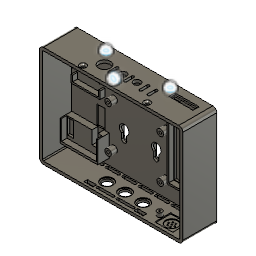
shell (Autodesk Fusion 360 design; units mm, degrees)
part number: 2026-11-14-09-25-26-611
part number: 2026-11-14-09-25-26-750
Autodesk Fusion 360 part; units mm, degrees
sketch "Sketch1" plane through (0, 0, 0) normal (0, 0, 1) x (1, 0, 0) in component "tray"
  arc A0 (67.5, 0) -> (71.5, 4) centre (67.5, 4) ccw
  line L0 (71.5, 4) -> (71.5, 97.3)
  arc A1 (71.5, 97.3) -> (67.5, 101.3) centre (67.5, 97.3) ccw
  line L1 (67.5, 101.3) -> (-67.5, 101.3)
  arc A2 (-67.5, 101.3) -> (-71.5, 97.3) centre (-67.5, 97.3) ccw
  line L2 (-71.5, 97.3) -> (-71.5, 4)
  arc A3 (-71.5, 4) -> (-67.5, 0) centre (-67.5, 4) ccw
  line L3 (-67.5, 0) -> (67.5, 0)
extrude "Extrude1" add sketch "Sketch1" along normal blind 34 from surface at 3 makes body 1 in component "tray"
sketch "Sketch3" plane through (0, 0, 0) normal (0, 0, 1) x (1, 0, 0) in component "tray"
  arc A0 (67.5, 3) -> (68.5, 4) centre (67.5, 4) ccw
  line L0 (68.5, 4) -> (68.5, 97.3)
  arc A1 (68.5, 97.3) -> (67.5, 98.3) centre (67.5, 97.3) ccw
  line L1 (67.5, 98.3) -> (-67.5, 98.3)
  arc A2 (-67.5, 98.3) -> (-68.5, 97.3) centre (-67.5, 97.3) ccw
  line L2 (-68.5, 97.3) -> (-68.5, 4)
  arc A3 (-68.5, 4) -> (-67.5, 3) centre (-67.5, 4) ccw
  line L3 (-67.5, 3) -> (67.5, 3)
extrude "Extrude2" add sketch "Sketch3" along normal blind 29.1 from surface at 2.9 separate body makes body 2 in component "tray"
combine "Combine1" operation cut target body 1 tool bodies 2 in component "tray"
sketch "Sketch4" plane through (0, 0, 0) normal (0, 0, 1) x (1, 0, 0) in component "tray"
  circle A0 centre (26, 38.5) radius 3.25
extrude "Extrude3" add sketch "Sketch4" along normal blind 6.01 from surface at 26 separate body makes body 3 in component "tray"
sketch "Sketch5" plane through (0, 0, 0) normal (0, 0, 1) x (1, 0, 0) in component "tray"
  circle A0 centre (26, 38.5) radius 1.3
extrude "Extrude4" add sketch "Sketch5" along normal blind 8.1 from surface at 25.9 separate body makes body 4 in component "tray"
sketch "Sketch6" plane through (0, 0, 0) normal (0, 0, 1) x (1, 0, 0) in component "tray"
  circle A0 centre (-26, 38.5) radius 3.25
extrude "Extrude5" add sketch "Sketch6" along normal blind 6.01 from surface at 26 separate body makes body 5 in component "tray"
sketch "Sketch7" plane through (0, 0, 0) normal (0, 0, 1) x (1, 0, 0) in component "tray"
  circle A0 centre (-26, 38.5) radius 1.3
extrude "Extrude6" add sketch "Sketch7" along normal blind 8.1 from surface at 25.9 separate body makes body 6 in component "tray"
sketch "Sketch8" plane through (0, 0, 0) normal (0, 0, 1) x (1, 0, 0) in component "tray"
  circle A0 centre (26, 81.5) radius 3.25
extrude "Extrude7" add sketch "Sketch8" along normal blind 6.01 from surface at 26 separate body makes body 7 in component "tray"
sketch "Sketch9" plane through (0, 0, 0) normal (0, 0, 1) x (1, 0, 0) in component "tray"
  circle A0 centre (26, 81.5) radius 1.3
extrude "Extrude8" add sketch "Sketch9" along normal blind 8.1 from surface at 25.9 separate body makes body 8 in component "tray"
sketch "Sketch10" plane through (0, 0, 0) normal (0, 0, 1) x (1, 0, 0) in component "tray"
  circle A0 centre (-26, 81.5) radius 3.25
extrude "Extrude9" add sketch "Sketch10" along normal blind 6.01 from surface at 26 separate body makes body 9 in component "tray"
sketch "Sketch11" plane through (0, 0, 0) normal (0, 0, 1) x (1, 0, 0) in component "tray"
  circle A0 centre (-26, 81.5) radius 1.3
extrude "Extrude10" add sketch "Sketch11" along normal blind 8.1 from surface at 25.9 separate body makes body 10 in component "tray"
sketch "Sketch12" plane through (0, 0, 0) normal (0, 0, 1) x (1, 0, 0) in component "tray"
  line L0 (37.1, -0.01) -> (37.1, 7.6)
  line L1 (37.1, 7.6) -> (-37.1, 7.6)
  line L2 (-37.1, 7.6) -> (-37.1, -0.01)
  line L3 (-37.1, -0.01) -> (37.1, -0.01)
extrude "Extrude11" add sketch "Sketch12" along normal blind 30.2 from surface at -15.1 separate body makes body 11 in component "tray"
sketch "Sketch13" plane through (0, 0, 0) normal (0, 0, 1) x (1, 0, 0) in component "tray"
  line L0 (35.5, 2.5) -> (35.5, 8.6)
  line L1 (35.5, 8.6) -> (-35.5, 8.6)
  line L2 (-35.5, 8.6) -> (-35.5, 2.5)
  line L3 (-35.5, 2.5) -> (35.5, 2.5)
extrude "Extrude12" add sketch "Sketch13" along normal blind 27 from surface at -13.5 separate body makes body 12 in component "tray"
sketch "Sketch14" plane through (0, 0, 0) normal (0, 0, 1) x (1, 0, 0) in component "tray"
  line L0 (35, 0.5) -> (35, 2.6)
  line L1 (35, 2.6) -> (-35, 2.6)
  line L2 (-35, 2.6) -> (-35, 0.5)
  line L3 (-35, 0.5) -> (35, 0.5)
extrude "Extrude13" add sketch "Sketch14" along normal blind 6 from surface at -13 separate body makes body 13 in component "tray"
sketch "Sketch15" plane through (0, 0, 0) normal (0, 0, 1) x (1, 0, 0) in component "tray"
  line L0 (35, 0.5) -> (35, 2.6)
  line L1 (35, 2.6) -> (-35, 2.6)
  line L2 (-35, 2.6) -> (-35, 0.5)
  line L3 (-35, 0.5) -> (35, 0.5)
extrude "Extrude14" add sketch "Sketch15" along normal blind 6 from surface at 7 separate body makes body 14 in component "tray"
sketch "Sketch16" plane through (0, 0, 0) normal (0, 0, 1) x (1, 0, 0) in component "tray"
  line L0 (-35.49, 2.5) -> (-35.49, 8.6)
  line L1 (-35.49, 8.6) -> (-37.2, 8.6)
  line L2 (-37.2, 8.6) -> (-37.2, 2.5)
  line L3 (-37.2, 2.5) -> (-35.49, 2.5)
extrude "Extrude15" add sketch "Sketch16" along normal blind 24.8 from surface at -12.4 separate body makes body 15 in component "tray"
combine "Combine2" operation cut target body 11 tool bodies 12 13 14 15 in component "tray"
move_body "Move1" bodies 11 to x (0, 1, 0) y (0, 0, -1) z (-1, 0, 0) at (49.5, 40.6, 32) in component "tray"
sketch "Sketch17" plane through (0, 0, 0) normal (0, 0, 1) x (1, 0, 0) in component "tray"
  line L0 (18.7, -0.01) -> (18.7, 11.6)
  line L1 (18.7, 11.6) -> (-18.7, 11.6)
  line L2 (-18.7, 11.6) -> (-18.7, -0.01)
  line L3 (-18.7, -0.01) -> (18.7, -0.01)
extrude "Extrude16" add sketch "Sketch17" along normal blind 21.8 from surface at -12.2 separate body makes body 16 in component "tray"
sketch "Sketch18" plane through (0, 0, 0) normal (0, 0, 1) x (1, 0, 0) in component "tray"
  line L0 (17.5, 6) -> (17.5, 11.7)
  line L1 (17.5, 11.7) -> (-17.5, 11.7)
  line L2 (-17.5, 11.7) -> (-17.5, 6)
  line L3 (-17.5, 6) -> (17.5, 6)
extrude "Extrude17" add sketch "Sketch18" along normal blind 20.6 from surface at -10 separate body makes body 17 in component "tray"
sketch "Sketch19" plane through (0, 0, 0) normal (0, 0, 1) x (1, 0, 0) in component "tray"
  line L0 (-7.5, -0.9) -> (-7.5, 6.01)
  line L1 (-7.5, 6.01) -> (-13.5, 6.01)
  line L2 (-13.5, 6.01) -> (-13.5, -0.9)
  line L3 (-13.5, -0.9) -> (-7.5, -0.9)
extrude "Extrude18" add sketch "Sketch19" along normal blind 14 from surface at -3.4 separate body makes body 18 in component "tray"
sketch "Sketch20" plane through (0, 0, 0) normal (0, 0, 1) x (1, 0, 0) in component "tray"
  line L0 (17, 3.6) -> (17, 6.01)
  line L1 (17, 6.01) -> (11, 6.01)
  line L2 (11, 6.01) -> (11, 3.6)
  line L3 (11, 3.6) -> (17, 3.6)
extrude "Extrude19" add sketch "Sketch20" along normal blind 15.2 from surface at -7 separate body makes body 19 in component "tray"
combine "Combine3" operation cut target body 16 tool bodies 17 18 19 in component "tray"
move_body "Move2" bodies 16 to x (-1, 0, 0) y (0, 0, -1) z (0, -1, 0) at (-49.5, 79.7, 32) in component "tray"
sketch "Sketch21" plane through (0, 0, 0) normal (0, 0, 1) x (1, 0, 0) in component "tray"
  line L0 (-6.5, -1.2) -> (-6.5, 0.01)
  line L1 (-6.5, 0.01) -> (-14.5, 0.01)
  line L2 (-14.5, 0.01) -> (-14.5, -1.2)
  line L3 (-14.5, -1.2) -> (-6.5, -1.2)
extrude "Extrude20" add sketch "Sketch21" along normal blind 18.5 from surface at 10 separate body makes body 20 in component "tray"
move_body "Move3" bodies 20 to x (-1, 0, 0) y (0, 0, -1) z (0, -1, 0) at (-49.5, 79.7, 32) in component "tray"
sketch "Sketch22" plane through (0, 0, 0) normal (0, 0, 1) x (1, 0, 0) in component "tray"
  line L0 (14.5, -0.01) -> (14.5, 5)
  line L1 (14.5, 5) -> (-14.5, 5)
  line L2 (-14.5, 5) -> (-14.5, -0.01)
  line L3 (-14.5, -0.01) -> (14.5, -0.01)
extrude "Extrude21" add sketch "Sketch22" along normal blind 21 from surface at -10.5 separate body makes body 21 in component "tray"
sketch "Sketch23" plane through (0, 0, 0) normal (0, 0, 1) x (1, 0, 0) in component "tray"
  line L0 (12.9, 0) -> (12.9, 5.1)
  line L1 (12.9, 5.1) -> (-12.9, 5.1)
  line L2 (-12.9, 5.1) -> (-12.9, 0)
  line L3 (-12.9, 0) -> (12.9, 0)
extrude "Extrude22" add sketch "Sketch23" along normal blind 17.8 from surface at -8.9 separate body makes body 22 in component "tray"
sketch "Sketch24" plane through (0, 0, 0) normal (0, 0, 1) x (1, 0, 0) in component "tray"
  line L0 (14.6, 0) -> (14.6, 5.1)
  line L1 (14.6, 5.1) -> (-14.6, 5.1)
  line L2 (-14.6, 5.1) -> (-14.6, 0)
  line L3 (-14.6, 0) -> (14.6, 0)
extrude "Extrude23" add sketch "Sketch24" along normal blind 6 from surface at -3 separate body makes body 23 in component "tray"
move_body "Move4" bodies 21 22 23 to x (1, 0, 0) y (0, 0, -1) z (0, 1, 0) at (-49.5, 30.5, 32) in component "tray"
sketch "Sketch25" plane through (0, 0, 0) normal (0, 1, 0) x (1, 0, 0) in component "tray"
  circle A0 centre (37.5, -14) radius 2.5
extrude "Extrude24" add sketch "Sketch25" along normal blind 4.01 from surface at 94.3 separate body makes body 24 in component "tray"
sketch "Sketch27" plane through (0, 0, 0) normal (0, 1, 0) x (1, 0, 0) in component "tray"
  circle A0 centre (37.5, -14) radius 0.8
extrude "Extrude25" add sketch "Sketch27" along normal blind 4.1 from surface at 94.2 separate body makes body 25 in component "tray"
sketch "Sketch28" plane through (0, 0, 0) normal (0, 1, 0) x (1, 0, 0) in component "tray"
  circle A0 centre (61.5, -14) radius 2.5
extrude "Extrude26" add sketch "Sketch28" along normal blind 4.01 from surface at 94.3 separate body makes body 26 in component "tray"
sketch "Sketch29" plane through (0, 0, 0) normal (0, 1, 0) x (1, 0, 0) in component "tray"
  circle A0 centre (61.5, -14) radius 0.8
extrude "Extrude27" add sketch "Sketch29" along normal blind 4.1 from surface at 94.2 separate body makes body 27 in component "tray"
combine "Combine4" operation add target body 1 tool bodies 3 5 7 9 11 16 21 24 26 in component "tray"
sketch "Sketch30" plane through (0, 0, 0) normal (0, 0, 1) x (1, 0, 0) in component "tray"
  circle A0 centre (16, 60) radius 4.75
extrude "Extrude28" add sketch "Sketch30" along normal blind 5.2 from surface at 31.9 separate body makes body 28 in component "tray"
sketch "Sketch31" plane through (0, 0, 0) normal (0, 0, 1) x (1, 0, 0) in component "tray"
  arc A0 (13.5, 60) -> (16, 57.5) centre (16, 60) ccw
  arc A1 (16, 57.5) -> (18.5, 60) centre (16, 60) ccw
  line L0 (18.5, 60) -> (18.5, 69)
  arc A2 (18.5, 69) -> (16, 71.5) centre (16, 69) ccw
  arc A3 (16, 71.5) -> (13.5, 69) centre (16, 69) ccw
  line L1 (13.5, 69) -> (13.5, 60)
extrude "Extrude29" add sketch "Sketch31" along normal blind 5.2 from surface at 31.9 separate body makes body 29 in component "tray"
sketch "Sketch32" plane through (0, 0, 0) normal (0, 0, 1) x (1, 0, 0) in component "tray"
  arc A0 (11.25, 60) -> (16, 55.25) centre (16, 60) ccw
  arc A1 (16, 55.25) -> (20.75, 60) centre (16, 60) ccw
  line L0 (20.75, 60) -> (20.75, 69)
  arc A2 (20.75, 69) -> (16, 73.75) centre (16, 69) ccw
  arc A3 (16, 73.75) -> (11.25, 69) centre (16, 69) ccw
  line L1 (11.25, 69) -> (11.25, 60)
extrude "Extrude30" add sketch "Sketch32" along normal blind 3.1 from surface at 34 separate body makes body 30 in component "tray"
sketch "Sketch33" plane through (0, 0, 0) normal (0, 0, 1) x (1, 0, 0) in component "tray"
  circle A0 centre (-16, 60) radius 4.75
extrude "Extrude31" add sketch "Sketch33" along normal blind 5.2 from surface at 31.9 separate body makes body 31 in component "tray"
sketch "Sketch34" plane through (0, 0, 0) normal (0, 0, 1) x (1, 0, 0) in component "tray"
  arc A0 (-18.5, 60) -> (-16, 57.5) centre (-16, 60) ccw
  arc A1 (-16, 57.5) -> (-13.5, 60) centre (-16, 60) ccw
  line L0 (-13.5, 60) -> (-13.5, 69)
  arc A2 (-13.5, 69) -> (-16, 71.5) centre (-16, 69) ccw
  arc A3 (-16, 71.5) -> (-18.5, 69) centre (-16, 69) ccw
  line L1 (-18.5, 69) -> (-18.5, 60)
extrude "Extrude32" add sketch "Sketch34" along normal blind 5.2 from surface at 31.9 separate body makes body 32 in component "tray"
sketch "Sketch35" plane through (0, 0, 0) normal (0, 0, 1) x (1, 0, 0) in component "tray"
  arc A0 (-20.75, 60) -> (-16, 55.25) centre (-16, 60) ccw
  arc A1 (-16, 55.25) -> (-11.25, 60) centre (-16, 60) ccw
  line L0 (-11.25, 60) -> (-11.25, 69)
  arc A2 (-11.25, 69) -> (-16, 73.75) centre (-16, 69) ccw
  arc A3 (-16, 73.75) -> (-20.75, 69) centre (-16, 69) ccw
  line L1 (-20.75, 69) -> (-20.75, 60)
extrude "Extrude33" add sketch "Sketch35" along normal blind 3.1 from surface at 34 separate body makes body 33 in component "tray"
sketch "Sketch36" plane through (0, 0, 0) normal (0, 0, 1) x (1, 0, 0) in component "tray"
  circle A0 centre (2.5, 8) radius 2.25
extrude "Extrude34" add sketch "Sketch36" along normal blind 5.2 from surface at 31.9 separate body makes body 34 in component "tray"
ref_plane "WorkPlane1" through (0, 0, 31.99) normal (0, 0, 1) x (1, 0, 0) in component "tray"
sketch "Sketch37" plane through (0, 0, 31.99) normal (0, 0, 1) x (1, 0, 0) in component "tray"
  circle A0 centre (2.5, 8) radius 4.51
ref_plane "WorkPlane2" through (0, 0, 34.25) normal (0, 0, 1) x (1, 0, 0) in component "tray"
sketch "Sketch38" plane through (0, 0, 34.25) normal (0, 0, 1) x (1, 0, 0) in component "tray"
  circle A0 centre (2.5, 8) radius 2.25
loft "Loft1" add profiles "Sketch37", "Sketch38" section 1 section 2 separate body makes body 35 in component "tray"
sketch "Sketch39" plane through (0, 0, 0) normal (0, 0, 1) x (1, 0, 0) in component "tray"
  circle A0 centre (-14, 12.5) radius 6
extrude "Extrude35" add sketch "Sketch39" along normal blind 4.5 from surface at 31.9 separate body makes body 36 in component "tray"
sketch "Sketch40" plane through (0, 0, 0) normal (0, 0, 1) x (1, 0, 0) in component "tray"
  circle A0 centre (14, 12.5) radius 6
extrude "Extrude36" add sketch "Sketch40" along normal blind 4.5 from surface at 31.9 separate body makes body 37 in component "tray"
sketch "Sketch41" plane through (0, 0, 0) normal (0, 1, 0) x (1, 0, 0) in component "tray"
  circle A0 centre (18, -17) radius 4.5
extrude "Extrude37" add sketch "Sketch41" along normal blind 3.2 from surface at 98.2 separate body makes body 38 in component "tray"
sketch "Sketch42" plane through (0, 0, 0) normal (0, 1, 0) x (1, 0, 0) in component "tray"
  circle A0 centre (0, -17) radius 4.5
extrude "Extrude38" add sketch "Sketch42" along normal blind 3.2 from surface at 98.2 separate body makes body 39 in component "tray"
sketch "Sketch43" plane through (0, 0, 0) normal (0, 1, 0) x (1, 0, 0) in component "tray"
  circle A0 centre (-18, -17) radius 4.5
extrude "Extrude39" add sketch "Sketch43" along normal blind 3.2 from surface at 98.2 separate body makes body 40 in component "tray"
sketch "Sketch44" plane through (0, 0, 0) normal (0, 1, 0) x (1, 0, 0) in component "tray"
  circle A0 centre (18, -17) radius 6
extrude "Extrude40" add sketch "Sketch44" along normal blind 0.9 from surface at 98.2 separate body makes body 41 in component "tray"
sketch "Sketch45" plane through (0, 0, 0) normal (0, 1, 0) x (1, 0, 0) in component "tray"
  circle A0 centre (0, -17) radius 6
extrude "Extrude41" add sketch "Sketch45" along normal blind 0.9 from surface at 98.2 separate body makes body 42 in component "tray"
sketch "Sketch46" plane through (0, 0, 0) normal (0, 1, 0) x (1, 0, 0) in component "tray"
  circle A0 centre (-18, -17) radius 6
extrude "Extrude42" add sketch "Sketch46" along normal blind 0.9 from surface at 98.2 separate body makes body 43 in component "tray"
sketch "Sketch47" plane through (0, 0, 0) normal (0, 1, 0) x (1, 0, 0) in component "tray"
  arc A0 (-1, -7.5) -> (-2.25, -6.25) centre (-2.25, -7.5) ccw
  arc A1 (-2.25, -8.75) -> (-1, -7.5) centre (-2.25, -7.5) ccw
  line L0 (-2.25, -8.75) -> (-17.75, -8.75)
  arc A2 (-19, -7.5) -> (-17.75, -8.75) centre (-17.75, -7.5) ccw
  arc A3 (-17.75, -6.25) -> (-19, -7.5) centre (-17.75, -7.5) ccw
  line L1 (-17.75, -6.25) -> (-2.25, -6.25)
extrude "Extrude43" add sketch "Sketch47" along normal blind 3.2 from surface at 98.2 separate body makes body 44 in component "tray"
sketch "Sketch48" plane through (0, 0, 0) normal (0, 1, 0) x (1, 0, 0) in component "tray"
  arc A0 (19, -7.5) -> (17.75, -6.25) centre (17.75, -7.5) ccw
  arc A1 (17.75, -8.75) -> (19, -7.5) centre (17.75, -7.5) ccw
  line L0 (17.75, -8.75) -> (2.25, -8.75)
  arc A2 (1, -7.5) -> (2.25, -8.75) centre (2.25, -7.5) ccw
  arc A3 (2.25, -6.25) -> (1, -7.5) centre (2.25, -7.5) ccw
  line L1 (2.25, -6.25) -> (17.75, -6.25)
extrude "Extrude44" add sketch "Sketch48" along normal blind 3.2 from surface at 98.2 separate body makes body 45 in component "tray"
sketch "Sketch49" plane through (0, 0, 0) normal (0, 1, 0) x (1, 0, 0) in component "tray"
  arc A0 (-50.125, -29.5) -> (-51.375, -28.25) centre (-51.375, -29.5) ccw
  arc A1 (-51.375, -30.75) -> (-50.125, -29.5) centre (-51.375, -29.5) ccw
  line L0 (-51.375, -30.75) -> (-63.25, -30.75)
  arc A2 (-64.5, -29.5) -> (-63.25, -30.75) centre (-63.25, -29.5) ccw
  arc A3 (-63.25, -28.25) -> (-64.5, -29.5) centre (-63.25, -29.5) ccw
  line L1 (-63.25, -28.25) -> (-51.375, -28.25)
extrude "Extrude45" add sketch "Sketch49" along normal blind 3.2 from surface at 98.2 separate body makes body 46 in component "tray"
sketch "Sketch50" plane through (0, 0, 0) normal (0, 1, 0) x (1, 0, 0) in component "tray"
  arc A0 (-33.75, -29.5) -> (-35, -28.25) centre (-35, -29.5) ccw
  arc A1 (-35, -30.75) -> (-33.75, -29.5) centre (-35, -29.5) ccw
  line L0 (-35, -30.75) -> (-46.875, -30.75)
  arc A2 (-48.125, -29.5) -> (-46.875, -30.75) centre (-46.875, -29.5) ccw
  arc A3 (-46.875, -28.25) -> (-48.125, -29.5) centre (-46.875, -29.5) ccw
  line L1 (-46.875, -28.25) -> (-35, -28.25)
extrude "Extrude46" add sketch "Sketch50" along normal blind 3.2 from surface at 98.2 separate body makes body 47 in component "tray"
sketch "Sketch51" plane through (0, 0, 0) normal (0, 1, 0) x (1, 0, 0) in component "tray"
  arc A0 (-17.375, -29.5) -> (-18.625, -28.25) centre (-18.625, -29.5) ccw
  arc A1 (-18.625, -30.75) -> (-17.375, -29.5) centre (-18.625, -29.5) ccw
  line L0 (-18.625, -30.75) -> (-30.5, -30.75)
  arc A2 (-31.75, -29.5) -> (-30.5, -30.75) centre (-30.5, -29.5) ccw
  arc A3 (-30.5, -28.25) -> (-31.75, -29.5) centre (-30.5, -29.5) ccw
  line L1 (-30.5, -28.25) -> (-18.625, -28.25)
extrude "Extrude47" add sketch "Sketch51" along normal blind 3.2 from surface at 98.2 separate body makes body 48 in component "tray"
sketch "Sketch52" plane through (0, 0, 0) normal (0, 1, 0) x (1, 0, 0) in component "tray"
  arc A0 (-1, -29.5) -> (-2.25, -28.25) centre (-2.25, -29.5) ccw
  arc A1 (-2.25, -30.75) -> (-1, -29.5) centre (-2.25, -29.5) ccw
  line L0 (-2.25, -30.75) -> (-14.125, -30.75)
  arc A2 (-15.375, -29.5) -> (-14.125, -30.75) centre (-14.125, -29.5) ccw
  arc A3 (-14.125, -28.25) -> (-15.375, -29.5) centre (-14.125, -29.5) ccw
  line L1 (-14.125, -28.25) -> (-2.25, -28.25)
extrude "Extrude48" add sketch "Sketch52" along normal blind 3.2 from surface at 98.2 separate body makes body 49 in component "tray"
sketch "Sketch53" plane through (0, 0, 0) normal (0, 1, 0) x (1, 0, 0) in component "tray"
  arc A0 (15.375, -29.5) -> (14.125, -28.25) centre (14.125, -29.5) ccw
  arc A1 (14.125, -30.75) -> (15.375, -29.5) centre (14.125, -29.5) ccw
  line L0 (14.125, -30.75) -> (2.25, -30.75)
  arc A2 (1, -29.5) -> (2.25, -30.75) centre (2.25, -29.5) ccw
  arc A3 (2.25, -28.25) -> (1, -29.5) centre (2.25, -29.5) ccw
  line L1 (2.25, -28.25) -> (14.125, -28.25)
extrude "Extrude49" add sketch "Sketch53" along normal blind 3.2 from surface at 98.2 separate body makes body 50 in component "tray"
sketch "Sketch54" plane through (0, 0, 0) normal (0, 1, 0) x (1, 0, 0) in component "tray"
  arc A0 (31.75, -29.5) -> (30.5, -28.25) centre (30.5, -29.5) ccw
  arc A1 (30.5, -30.75) -> (31.75, -29.5) centre (30.5, -29.5) ccw
  line L0 (30.5, -30.75) -> (18.625, -30.75)
  arc A2 (17.375, -29.5) -> (18.625, -30.75) centre (18.625, -29.5) ccw
  arc A3 (18.625, -28.25) -> (17.375, -29.5) centre (18.625, -29.5) ccw
  line L1 (18.625, -28.25) -> (30.5, -28.25)
extrude "Extrude50" add sketch "Sketch54" along normal blind 3.2 from surface at 98.2 separate body makes body 51 in component "tray"
sketch "Sketch55" plane through (0, 0, 0) normal (0, 1, 0) x (1, 0, 0) in component "tray"
  arc A0 (48.125, -29.5) -> (46.875, -28.25) centre (46.875, -29.5) ccw
  arc A1 (46.875, -30.75) -> (48.125, -29.5) centre (46.875, -29.5) ccw
  line L0 (46.875, -30.75) -> (35, -30.75)
  arc A2 (33.75, -29.5) -> (35, -30.75) centre (35, -29.5) ccw
  arc A3 (35, -28.25) -> (33.75, -29.5) centre (35, -29.5) ccw
  line L1 (35, -28.25) -> (46.875, -28.25)
extrude "Extrude51" add sketch "Sketch55" along normal blind 3.2 from surface at 98.2 separate body makes body 52 in component "tray"
sketch "Sketch56" plane through (0, 0, 0) normal (0, 1, 0) x (1, 0, 0) in component "tray"
  arc A0 (64.5, -29.5) -> (63.25, -28.25) centre (63.25, -29.5) ccw
  arc A1 (63.25, -30.75) -> (64.5, -29.5) centre (63.25, -29.5) ccw
  line L0 (63.25, -30.75) -> (51.375, -30.75)
  arc A2 (50.125, -29.5) -> (51.375, -30.75) centre (51.375, -29.5) ccw
  arc A3 (51.375, -28.25) -> (50.125, -29.5) centre (51.375, -29.5) ccw
  line L1 (51.375, -28.25) -> (63.25, -28.25)
extrude "Extrude52" add sketch "Sketch56" along normal blind 3.2 from surface at 98.2 separate body makes body 53 in component "tray"
sketch "Sketch57" plane through (0, 0, 0) normal (0, 0, 1) x (1, 0, 0) in component "tray"
  line L0 (-20.5, 98.2) -> (-20.5, 101.4)
  line L1 (-20.5, 101.4) -> (-29.5, 101.4)
  line L2 (-29.5, 101.4) -> (-29.5, 98.2)
  line L3 (-29.5, 98.2) -> (-20.5, 98.2)
extrude "Extrude53" add sketch "Sketch57" along normal blind 3.5 from surface at 5.5 separate body makes body 54 in component "tray"
sketch "Sketch58" plane through (0, 0, 0) normal (0, 0, 1) x (1, 0, 0) in component "tray"
  line L0 (29.5, 98.2) -> (29.5, 101.4)
  line L1 (29.5, 101.4) -> (20.5, 101.4)
  line L2 (20.5, 101.4) -> (20.5, 98.2)
  line L3 (20.5, 98.2) -> (29.5, 98.2)
extrude "Extrude54" add sketch "Sketch58" along normal blind 3.5 from surface at 5.5 separate body makes body 55 in component "tray"
sketch "Sketch59" plane through (0, 0, 0) normal (0, 1, 0) x (1, 0, 0) in component "tray"
  line L0 (58.4, -6.1) -> (58.4, -21.9)
  line L1 (58.4, -21.9) -> (40.6, -21.9)
  line L2 (40.6, -21.9) -> (40.6, -6.1)
  line L3 (40.6, -6.1) -> (58.4, -6.1)
extrude "Extrude55" add sketch "Sketch59" along normal blind 1.1 from surface at 98.2 separate body makes body 56 in component "tray"
sketch "Sketch60" plane through (0, 0, 0) normal (0, 1, 0) x (1, 0, 0) in component "tray"
  circle A0 centre (49.5, -14) radius 6
extrude "Extrude56" add sketch "Sketch60" along normal blind 0.81 from surface at 99.29 separate body makes body 57 in component "tray"
sketch "Sketch61" plane through (0, 0, 0) normal (0, 1, 0) x (1, 0, 0) in component "tray"
  circle A0 centre (49.5, -14) radius 0.75
extrude "Extrude57" add sketch "Sketch61" along normal blind 1.31 from surface at 100.09 separate body makes body 58 in component "tray"
sketch "Sketch62" plane through (0, 0, 0) normal (0, 1, 0) x (1, 0, 0) in component "tray"
  circle A0 centre (52.5, -14) radius 0.75
extrude "Extrude58" add sketch "Sketch62" along normal blind 1.31 from surface at 100.09 separate body makes body 59 in component "tray"
sketch "Sketch63" plane through (0, 0, 0) normal (0, 1, 0) x (1, 0, 0) in component "tray"
  circle A0 centre (51, -16.5981) radius 0.75
extrude "Extrude59" add sketch "Sketch63" along normal blind 1.31 from surface at 100.09 separate body makes body 60 in component "tray"
sketch "Sketch64" plane through (0, 0, 0) normal (0, 1, 0) x (1, 0, 0) in component "tray"
  circle A0 centre (48, -16.5981) radius 0.75
extrude "Extrude60" add sketch "Sketch64" along normal blind 1.31 from surface at 100.09 separate body makes body 61 in component "tray"
sketch "Sketch65" plane through (0, 0, 0) normal (0, 1, 0) x (1, 0, 0) in component "tray"
  circle A0 centre (46.5, -14) radius 0.75
extrude "Extrude61" add sketch "Sketch65" along normal blind 1.31 from surface at 100.09 separate body makes body 62 in component "tray"
sketch "Sketch66" plane through (0, 0, 0) normal (0, 1, 0) x (1, 0, 0) in component "tray"
  circle A0 centre (48, -11.4019) radius 0.75
extrude "Extrude62" add sketch "Sketch66" along normal blind 1.31 from surface at 100.09 separate body makes body 63 in component "tray"
sketch "Sketch67" plane through (0, 0, 0) normal (0, 1, 0) x (1, 0, 0) in component "tray"
  circle A0 centre (51, -11.4019) radius 0.75
extrude "Extrude63" add sketch "Sketch67" along normal blind 1.31 from surface at 100.09 separate body makes body 64 in component "tray"
sketch "Sketch68" plane through (0, 0, 0) normal (0, 1, 0) x (1, 0, 0) in component "tray"
  circle A0 centre (-22, -18.4) radius 6
extrude "Extrude64" add sketch "Sketch68" along normal blind 3.2 from surface at -0.1 separate body makes body 65 in component "tray"
sketch "Sketch69" plane through (0, 0, 0) normal (0, 1, 0) x (1, 0, 0) in component "tray"
  circle A0 centre (-4.5, -19.4) radius 3.5
extrude "Extrude65" add sketch "Sketch69" along normal blind 3.2 from surface at -0.1 separate body makes body 66 in component "tray"
sketch "Sketch70" plane through (0, 0, 0) normal (0, 1, 0) x (1, 0, 0) in component "tray"
  circle A0 centre (9.5, -19.4) radius 3.5
extrude "Extrude66" add sketch "Sketch70" along normal blind 3.2 from surface at -0.1 separate body makes body 67 in component "tray"
sketch "Sketch71" plane through (0, 0, 0) normal (0, 1, 0) x (1, 0, 0) in component "tray"
  arc A0 (-13, -13.4) -> (-14.25, -14.65) centre (-13, -14.65) ccw
  arc A1 (-11.75, -14.65) -> (-13, -13.4) centre (-13, -14.65) ccw
  line L0 (-11.75, -14.65) -> (-11.75, -22.15)
  arc A2 (-13, -23.4) -> (-11.75, -22.15) centre (-13, -22.15) ccw
  arc A3 (-14.25, -22.15) -> (-13, -23.4) centre (-13, -22.15) ccw
  line L1 (-14.25, -22.15) -> (-14.25, -14.65)
extrude "Extrude67" add sketch "Sketch71" along normal blind 3.2 from surface at -0.1 separate body makes body 68 in component "tray"
sketch "Sketch72" plane through (0, 0, 0) normal (0, 1, 0) x (1, 0, 0) in component "tray"
  arc A0 (2.5, -13.4) -> (1.25, -14.65) centre (2.5, -14.65) ccw
  arc A1 (3.75, -14.65) -> (2.5, -13.4) centre (2.5, -14.65) ccw
  line L0 (3.75, -14.65) -> (3.75, -22.15)
  arc A2 (2.5, -23.4) -> (3.75, -22.15) centre (2.5, -22.15) ccw
  arc A3 (1.25, -22.15) -> (2.5, -23.4) centre (2.5, -22.15) ccw
  line L1 (1.25, -22.15) -> (1.25, -14.65)
extrude "Extrude68" add sketch "Sketch72" along normal blind 3.2 from surface at -0.1 separate body makes body 69 in component "tray"
sketch "Sketch73" plane through (0, 0, 0) normal (0, 1, 0) x (1, 0, 0) in component "tray"
  arc A0 (18, -13.4) -> (16.75, -14.65) centre (18, -14.65) ccw
  arc A1 (19.25, -14.65) -> (18, -13.4) centre (18, -14.65) ccw
  line L0 (19.25, -14.65) -> (19.25, -22.15)
  arc A2 (18, -23.4) -> (19.25, -22.15) centre (18, -22.15) ccw
  arc A3 (16.75, -22.15) -> (18, -23.4) centre (18, -22.15) ccw
  line L1 (16.75, -22.15) -> (16.75, -14.65)
extrude "Extrude69" add sketch "Sketch73" along normal blind 3.2 from surface at -0.1 separate body makes body 70 in component "tray"
sketch "Sketch74" plane through (0, 0, 0) normal (0, 1, 0) x (1, 0, 0) in component "tray"
  arc A0 (26, -13.4) -> (24.75, -14.65) centre (26, -14.65) ccw
  arc A1 (27.25, -14.65) -> (26, -13.4) centre (26, -14.65) ccw
  line L0 (27.25, -14.65) -> (27.25, -22.15)
  arc A2 (26, -23.4) -> (27.25, -22.15) centre (26, -22.15) ccw
  arc A3 (24.75, -22.15) -> (26, -23.4) centre (26, -22.15) ccw
  line L1 (24.75, -22.15) -> (24.75, -14.65)
extrude "Extrude70" add sketch "Sketch74" along normal blind 3.2 from surface at -0.1 separate body makes body 71 in component "tray"
sketch "Sketch75" plane through (0, 0, 0) normal (0, 1, 0) x (1, 0, 0) in component "tray"
  circle A0 centre (-32, -7) radius 1.7
extrude "Extrude71" add sketch "Sketch75" along normal blind 3.2 from surface at -0.1 separate body makes body 72 in component "tray"
ref_plane "WorkPlane3" through (0, -0.1, 0) normal (0, 1, 0) x (0, 0, 1) in component "tray"
sketch "Sketch76" plane through (0, -0.1, 0) normal (0, 1, 0) x (1, 0, 0) in component "tray"
  circle A0 centre (-32, -7) radius 3.35
ref_plane "WorkPlane4" through (0, 1.55, 0) normal (0, 1, 0) x (0, 0, 1) in component "tray"
sketch "Sketch77" plane through (0, 1.55, 0) normal (0, 1, 0) x (1, 0, 0) in component "tray"
  circle A0 centre (-32, -7) radius 1.7
loft "Loft2" add profiles "Sketch76", "Sketch77" section 1 section 2 separate body makes body 73 in component "tray"
sketch "Sketch78" plane through (0, 0, 0) normal (0, 1, 0) x (1, 0, 0) in component "tray"
  circle A0 centre (32, -7) radius 1.7
extrude "Extrude72" add sketch "Sketch78" along normal blind 3.2 from surface at -0.1 separate body makes body 74 in component "tray"
ref_plane "WorkPlane5" through (0, -0.1, 0) normal (0, 1, 0) x (0, 0, 1) in component "tray"
sketch "Sketch79" plane through (0, -0.1, 0) normal (0, 1, 0) x (1, 0, 0) in component "tray"
  circle A0 centre (32, -7) radius 3.35
ref_plane "WorkPlane6" through (0, 1.55, 0) normal (0, 1, 0) x (0, 0, 1) in component "tray"
sketch "Sketch80" plane through (0, 1.55, 0) normal (0, 1, 0) x (1, 0, 0) in component "tray"
  circle A0 centre (32, -7) radius 1.7
loft "Loft3" add profiles "Sketch79", "Sketch80" section 1 section 2 separate body makes body 75 in component "tray"
sketch "Sketch81" plane through (0, 0, 0) normal (0, 0, 1) x (1, 0, 0) in component "tray"
  line L0 (61.5, -0.1) -> (61.5, 3.1)
  line L1 (61.5, 3.1) -> (37.5, 3.1)
  line L2 (37.5, 3.1) -> (37.5, -0.1)
  line L3 (37.5, -0.1) -> (61.5, -0.1)
extrude "Extrude73" add sketch "Sketch81" along normal blind 6 from surface at 23.25 separate body makes body 76 in component "tray"
sketch "Sketch82" plane through (0, 0, 0) normal (0, 0, 1) x (1, 0, 0) in component "tray"
  line L0 (63.5, 1.8) -> (63.5, 3.1)
  line L1 (63.5, 3.1) -> (35.5, 3.1)
  line L2 (35.5, 3.1) -> (35.5, 1.8)
  line L3 (35.5, 1.8) -> (63.5, 1.8)
extrude "Extrude74" add sketch "Sketch82" along normal blind 10 from surface at 21.25 separate body makes body 77 in component "tray"
combine "Combine5" operation cut target body 1 tool bodies 4 6 8 10 20 28 29 30 31 32 33 34 35 36 37 22 23 25 27 38 39 40 41 42 43 44 45 46 47 48 49 50 51 52 53 54 55 56 57 58 59 60 61 62 63 64 65 66 67 68 69 70 71 72 73 74 75 76 77 in component "tray"
move_body "Move5" bodies 1 to x (1, 0, 0) y (0, -1, 0) z (0, 0, -1) at (0, 0, 37) in component "tray"
component "tray" placed x (1, 0, 0) y (0, 1, 0) z (0, 0, 1) at (0, 0, 0)
equation "ref_box_w = 143 mm" comment "outer width"
equation "ref_box_h = 101.3 mm" comment "(derived) outer height"
equation "ref_box_d = 37 mm" comment "(derived) depth, front face to the wall"
equation "ref_wall = 3 mm" comment "walls and panel"
equation "ref_plate_z = 32 mm" comment "(derived) back plate front face, box-local z"
equation "ref_face_top_y = 97 mm" comment "(derived) amp faceplate front face, box-local y"
equation "ref_knob_z = 17 mm" comment "(derived) knob shafts, box-local z"
equation "ref_connector_y = 22 mm" comment "(derived) amp connector faces, box-local y"
equation "ref_btn_x = 0 mm" comment "button axis on the front face, x (+ = viewer left)"
equation "ref_btn_y = 75 mm" comment "button axis on the front face, y"
equation "ref_mic_x = 49.5 mm" comment "mic port on the front face, x"
equation "ref_mic_y = 14 mm" comment "mic port on the front face, y"
equation "ref_clr = 0.4 mm" comment "global clearance"
named bodies: "tray", "cavity", "standoff", "standoff pilot", "standoff 2", "standoff pilot 2", "standoff 3", "standoff pilot 3", "standoff 4", "standoff pilot 4", "devkit pocket", "board cavity", "pin relief", "pin relief 2", "USB notch", "DAC seat", "DAC cavity", "socket recess", "plug groove", "MP1584 pocket", "MP cavity", "MP wire exits", "mic post", "mic post pilot", "mic post 2", "mic post pilot 2", "keyhole entry", "keyhole slot", "keyhole pocket", "keyhole entry 2", "keyhole slot 2", "keyhole pocket 2", "locking screw", "locking countersink", "knock-out", "knock-out 2", "knob hole", "knob hole 2", "knob hole 3", "nut recess", "nut recess 2", "nut recess 3", "top vent", "top vent 2", "top vent 3", "top vent 4", "top vent 5", "top vent 6", "top vent 7", "top vent 8", "top vent 9", "top vent 10", "hook window", "hook window 2", "mic board recess", "gasket seat", "mic grille", "mic grille 2", "mic grille 3", "mic grille 4", "mic grille 5", "mic grille 6", "mic grille 7", "DC plug hole", "speaker hole", "speaker hole 2", "bottom vent", "bottom vent 2", "bottom vent 3", "bottom vent 4", "panel screw", "panel screw countersink", "panel screw 2", "panel screw countersink 2", "USB window", "USB panel thinning"
